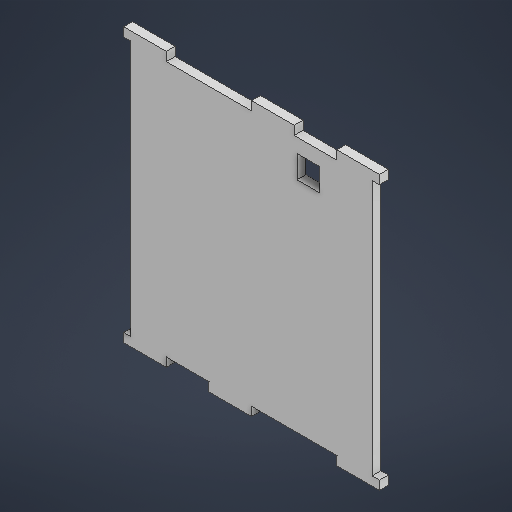
# Autodesk Inventor part: tapasuperior
Saved by Autodesk Inventor 2027.1 (Build 311270010, 270A)
## iProperties
Created: 2026-10-12
Part Number: tapasuperior
Material: Generic
Document SubType Name: Modeling
Designer: MineS
Density: 1 g/cm^3
Appearance: Default
Author: MineS
Autodesk Inventor part; units mm, degrees
ref_plane "YZ Plane" through (0, 0, 0) normal (1, 0, 0) x (0, 1, 0)
ref_plane "XZ Plane" through (0, 0, 0) normal (0, 1, 0) x (-1, 0, 0)
ref_plane "XY Plane" through (0, 0, 0) normal (0, 0, 1) x (1, 0, 0)
sketch "Sketch1" plane through (0, 0, 0) normal (0, 0, 1) x (1, 0, 0)
  line L0 (60, 0) -> (75, 0) projected
  line L1 (60, 3.125) -> (75, 3.125) projected
  line L2 (45, -93.125) -> (75, -93.125) projected
  line L3 (45, -90) -> (75, -90) projected
  line L4 (87.899, -90) -> (87.899, 0) projected
  line L5 (1.9696, 0) -> (1.9696, -90) projected
  line L6 (87.899, 0) -> (1.9696, 0)
  line L7 (1.9696, 0) -> (1.9696, -90)
  line L8 (1.9696, -90) -> (87.899, -90)
  line L9 (87.899, -90) -> (87.899, 0)
  line L10 (60, 3.125) -> (60, 0) projected
  line L11 (75, 0) -> (75, 3.125) projected
  line L12 (45, -90) -> (45, -93.125) projected
  line L13 (75, -93.125) -> (75, -90) projected
  line L14 (30, -90) -> (45, -90) projected
  line L15 (30, -93.125) -> (30, -90) projected
  line L16 (45, -93.125) -> (30, -93.125) projected
  line L17 (45, -93.125) -> (45, -90) projected
  line L18 (30, -93.125) -> (30, -90) projected
  line L19 (15, -90) -> (30, -90) projected
  line L20 (15, -90) -> (15, -93.125) projected
  line L21 (15, -93.125) -> (30, -93.125) projected
  line L22 (0, -90) -> (15, -90) projected
  line L23 (0, -93.125) -> (0, -90) projected
  line L24 (15, -93.125) -> (0, -93.125) projected
  line L25 (15, -93.125) -> (15, -90) projected
  line L26 (0, 3.125) -> (15, 3.125) projected
  line L27 (0, 3.125) -> (0, 0) projected
  line L28 (15, 0) -> (0, 0) projected
  line L29 (15, 3.125) -> (15, 0) projected
  line L30 (45, 0) -> (45, 3.125) projected
  line L31 (15, 3.125) -> (45, 3.125) projected
  line L32 (15, 3.125) -> (15, 0) projected
  line L33 (15, 0) -> (45, 0) projected
  line L34 (45, 3.125) -> (60, 3.125) projected
  line L35 (45, 3.125) -> (45, 0) projected
  line L36 (60, 0) -> (45, 0) projected
  line L37 (60, 3.125) -> (60, 0) projected
  line L38 (75, 3.125) -> (90, 3.125) projected
  line L39 (75, 3.125) -> (75, 0) projected
  line L40 (90, 0) -> (75, 0) projected
  line L41 (90, 3.125) -> (90, 0) projected
  line L42 (75, -90) -> (90, -90) projected
  line L43 (75, -93.125) -> (75, -90) projected
  line L44 (90, -93.125) -> (75, -93.125) projected
  line L45 (90, -93.125) -> (90, -90) projected
  line L46 (87.899, 0) -> (1.9696, 0)
  line L47 (1.9696, 0) -> (1.9696, -90)
  line L48 (1.9696, -90) -> (87.899, -90)
  line L49 (87.899, -90) -> (87.899, 0)
  line L50 (2.4696, -90) -> (2.4696, 0)
  line L51 (87.399, -90) -> (87.399, 0)
  dimension "d2" = 0.5
  dimension "d3" = 0.5
  constraints: 20 end point, 4 parallel, 4 perpendicular, 4 point on line, 2 horizontal, 2 other
  measures "d2" distance between parallel lines of L7 L50
  measures "d3" distance between parallel lines of L4 L51
extrude "Extrusion1" add sketch "Sketch1" against normal blind 3.125 contours L0 L6 L51 L8 L3 L50 | L6 L30 L34 L10 | L11 L38 L41 L40 L6 | L6 L28 L27 L26 L29 | L8 L42 L45 L44 L13 | L8 L20 L24 L23 L22 | L12 L16 L15 L8
sketch "Sketch2" plane through (0, 0, 0) normal (0, 0, 1) x (1, 0, 0)
  line L0 (69, -5) -> (61, -5)
  line L1 (61, -5) -> (61, -13)
  line L2 (61, -13) -> (69, -13)
  line L3 (69, -13) -> (69, -5)
  line L4 (75, 3.125) -> (75, 0) projected
  line L5 (75, 0) -> (60, 0) projected
  point P0 (0, 0)
  point P1 (65, -5)
  dimension "d4" = 8
  dimension "d5" = 8
  dimension "d6" = 10
  dimension "d7" = 5
  constraints: 8 end point, 2 parallel, 1 horizontal, 1 midpoint, 1 perpendicular
  measures "d4" distance of L2.end L0.start
  measures "d5" distance of L1.end L2.end
  measures "d6" distance from line of L4 point (65, -5)
  measures "d7" distance between parallel lines of L5 L0
extrude "Extrusion2" cut sketch "Sketch2" against normal blind 3.125
body "Solid1"
